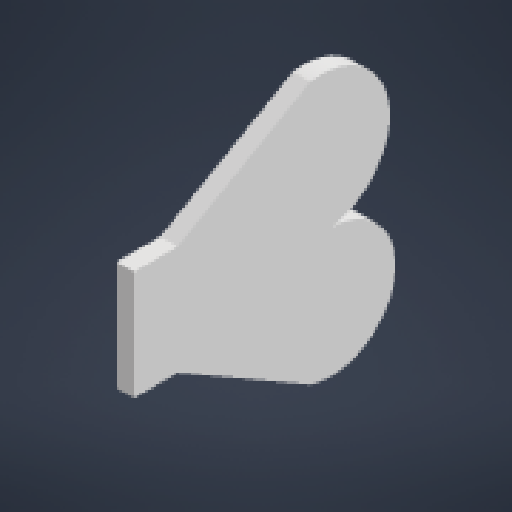
# Autodesk Inventor part: tail
Saved by Autodesk Inventor 2026.2 (Build 302298000, 298)
## iProperties
Created: 2026-04-15
Part Number: tail
Material: Generic
Document SubType Name: Modeling
Designer: thita
Density: 1 g/cm^3
Appearance: Default
Author: thita
Autodesk Inventor part; units mm, degrees
ref_plane "YZ Plane" through (0, 0, 0) normal (1, 0, 0) x (0, 1, 0)
ref_plane "XZ Plane" through (0, 0, 0) normal (0, 1, 0) x (-1, 0, 0)
ref_plane "XY Plane" through (0, 0, 0) normal (0, 0, 1) x (1, 0, 0)
sketch "Sketch1" plane through (0, 0, 0) normal (0, 0, 1) x (1, 0, 0)
  line L0 (4, -25) -> (4, 25)
  line L1 (4, 25) -> (-4, 25)
  line L2 (-4, 25) -> (-4, -25)
  line L3 (-4, -25) -> (4, -25)
  line L4 (4, -25) -> (-4, 25) construction
  line L5 (4, 25) -> (-4, -25) construction
  point P0 (0, 0)
  dimension "d0" = 50
  dimension "d1" = 8
  constraints: 12 end point, 2 midpoint, 2 parallel, 1 perpendicular, 1 vertical
  measures "d0" distance of L0.start L0.end
  measures "d1" distance of L1.end L0.end
extrude "Extrusion1" add sketch "Sketch1" against normal blind 20
sketch "Sketch2" plane through (4, -25, 0) normal (1, 0, 0) x (0, 0, -1)
  line L0 (20, 50) -> (36.4101, 50)
  line L1 (20, 50) -> (20, 0) projected
  line L2 (20, 50) -> (80.6394, 84.9695)
  arc A0 (90, 22.5) -> (80.6394, 84.9695) centre (85.3197, 53.7347) ccw
  line L3 (20, 0) -> (80.6394, -34.9695)
  arc A1 (80.6394, -34.9695) -> (90, 22.5) centre (90, -6.9971) ccw
  point P0 (0, 25)
  dimension "d4" = 70
  constraints: 6 end point, 4 point on circle, 2 centre point, 1 horizontal
  measures "d4" distance of L0.start L2.end
extrude "Extrusion2" add sketch "Sketch2" against normal up to surface (8 mm away)
body "Solid1"
